Autodesk Fusion 360 part; units mm, degrees
(part 2 of 2)
sketch "Esboço2 (11)" plane through (83, 0, 0) normal (1, 0, 0) x (0, 0, -1) in component "08 / Cursor lateral ON OFF / aciona chave da placa"
  line L0 (7, 35.82) -> (11, 35.82)
  line L1 (11.5, 36.32) -> (11.5, 39.32)
  line L2 (11, 39.82) -> (7, 39.82)
  line L3 (6.5, 39.32) -> (6.5, 36.32)
  arc A0 (11, 35.82) -> (11.5, 36.32) centre (11, 36.32) ccw
  arc A1 (11.5, 39.32) -> (11, 39.82) centre (11, 39.32) ccw
  arc A2 (7, 39.82) -> (6.5, 39.32) centre (7, 39.32) ccw
  arc A3 (6.5, 36.32) -> (7, 35.82) centre (7, 36.32) ccw
extrude "Ponte do cursor ate a chave" add sketch "Esboço2 (11)" along normal blind 6 bodies 17 in component "08 / Cursor lateral ON OFF / aciona chave da placa"
ref_plane "Plano de trabalho3" through (85, 0, 0) normal (1, 0, 0) x (0, 1, 0) in component "08 / Cursor lateral ON OFF / aciona chave da placa"
sketch "Esboço3 (7)" plane through (85, 0, 0) normal (1, 0, 0) x (0, 0, -1) in component "08 / Cursor lateral ON OFF / aciona chave da placa"
  line L0 (2, 32.82) -> (16, 32.82)
  line L1 (18, 34.82) -> (18, 40.82)
  line L2 (16, 42.82) -> (2, 42.82)
  line L3 (0, 40.82) -> (0, 34.82)
  arc A0 (16, 32.82) -> (18, 34.82) centre (16, 34.82) ccw
  arc A1 (18, 40.82) -> (16, 42.82) centre (16, 40.82) ccw
  arc A2 (2, 42.82) -> (0, 40.82) centre (2, 40.82) ccw
  arc A3 (0, 34.82) -> (2, 32.82) centre (2, 34.82) ccw
extrude "Flange de retencao" add sketch "Esboço3 (7)" along normal blind 1.2 bodies 17 in component "08 / Cursor lateral ON OFF / aciona chave da placa"
ref_plane "Plano de trabalho4" through (82, 0, 0) normal (1, 0, 0) x (0, 1, 0) in component "08 / Cursor lateral ON OFF / aciona chave da placa"
sketch "Esboço4 (5)" plane through (82, 0, 0) normal (1, 0, 0) x (0, 0, -1) in component "08 / Cursor lateral ON OFF / aciona chave da placa"
  line L0 (7, 35.82) -> (11, 35.82)
  line L1 (11.5, 36.32) -> (11.5, 39.32)
  line L2 (11, 39.82) -> (7, 39.82)
  line L3 (6.5, 39.32) -> (6.5, 36.32)
  arc A0 (11, 35.82) -> (11.5, 36.32) centre (11, 36.32) ccw
  arc A1 (11.5, 39.32) -> (11, 39.82) centre (11, 39.32) ccw
  arc A2 (7, 39.82) -> (6.5, 39.32) centre (7, 39.32) ccw
  arc A3 (6.5, 36.32) -> (7, 35.82) centre (7, 36.32) ccw
extrude "Garfo chave / medir lingueta" add sketch "Esboço4 (5)" along normal blind 2.2 bodies 17 in component "08 / Cursor lateral ON OFF / aciona chave da placa"
ref_plane "Plano de trabalho5" through (81.9, 0, 0) normal (1, 0, 0) x (0, 1, 0) in component "08 / Cursor lateral ON OFF / aciona chave da placa"
sketch "Esboço5 (5)" plane through (81.9, 0, 0) normal (1, 0, 0) x (0, 0, -1) in component "08 / Cursor lateral ON OFF / aciona chave da placa"
  line L0 (8.3, 36.82) -> (9.7, 36.82)
  line L1 (10, 37.12) -> (10, 38.52)
  line L2 (9.7, 38.82) -> (8.3, 38.82)
  line L3 (8, 38.52) -> (8, 37.12)
  arc A0 (9.7, 36.82) -> (10, 37.12) centre (9.7, 37.12) ccw
  arc A1 (10, 38.52) -> (9.7, 38.82) centre (9.7, 38.52) ccw
  arc A2 (8.3, 38.82) -> (8, 38.52) centre (8.3, 38.52) ccw
  arc A3 (8, 37.12) -> (8.3, 36.82) centre (8.3, 37.12) ccw
extrude "Rasgo para lingueta original" cut sketch "Esboço5 (5)" along normal blind 2.3 bodies 17 in component "08 / Cursor lateral ON OFF / aciona chave da placa"
ref_plane "Plano de trabalho1" through (0, 0, -3) normal (0, 0, 1) x (1, 0, 0) in component "09 / Bicos MIC frontais / dutos a medir"
sketch "Esboço1 (12)" plane through (0, 0, -3) normal (0, 0, 1) x (1, 0, 0) in component "09 / Bicos MIC frontais / dutos a medir"
  circle A0 centre (-68, -52.2) radius 1.8
  circle A1 centre (-68, -52.2) radius 1
extrude "Extrusão1" add sketch "Esboço1 (12)" against normal blind 3 separate body makes body 18 in component "09 / Bicos MIC frontais / dutos a medir"
ref_plane "Plano de trabalho2" through (0, 0, -3) normal (0, 0, 1) x (1, 0, 0) in component "09 / Bicos MIC frontais / dutos a medir"
sketch "Esboço2 (12)" plane through (0, 0, -3) normal (0, 0, 1) x (1, 0, 0) in component "09 / Bicos MIC frontais / dutos a medir"
  circle A0 centre (73, -52.2) radius 1.8
  circle A1 centre (73, -52.2) radius 1
extrude "Extrusão2'" add sketch "Esboço2 (12)" against normal blind 3 separate body makes body 19 in component "09 / Bicos MIC frontais / dutos a medir"
component "01 / Moldura fina / microfones frontais" placed x (1, 0, 0) y (0, 1, 0) z (0, 0, 1) at (0, 0, 0)
component "REF / Vidro 164.28 x 99.17 / area ativa assimetrica" placed x (1, 0, 0) y (0, 0.309017, 0.951057) z (0, -0.951057, 0.309017) at (0, 16.9959, 52.3081)
component "02 / Corpo em cunha / apoio direto na mesa" placed x (1, 0, 0) y (0, 0.309017, 0.951057) z (0, -0.951057, 0.309017) at (0, 16.9959, 52.3081)
component "03 / Tampa traseira / grelha alto-falante + ventilacao" placed x (1, 0, 0) y (0, 0.309017, 0.951057) z (0, -0.951057, 0.309017) at (0, 16.9959, 52.3081)
component "REF / PCB 164 x 97 / pitch furos 156 x 89" placed x (1, 0, 0) y (0, 0.309017, 0.951057) z (0, -0.951057, 0.309017) at (0, 16.9959, 52.3081)
component "04 / Apoios PCB / distancias da foto" placed x (1, 0, 0) y (0, 0.309017, 0.951057) z (0, -0.951057, 0.309017) at (0, 16.9959, 52.3081)
component "REF / Alto-falante TRASEIRO / dimensoes provisÃ³rias" placed x (1, 0, 0) y (0, 0.309017, 0.951057) z (0, -0.951057, 0.309017) at (0, 16.9959, 52.3081)
component "05 / Berco traseiro alto-falante / medir encaixe" placed x (1, 0, 0) y (0, 0.309017, 0.951057) z (0, -0.951057, 0.309017) at (0, 16.9959, 52.3081)
component "06 / Volume + e - / teclas no topo" placed x (1, 0, 0) y (0, 0.309017, 0.951057) z (0, -0.951057, 0.309017) at (0, 16.9959, 52.3081)
component "07 / Suporte dos switches volume / eletrica pendente" placed x (1, 0, 0) y (0, 0.309017, 0.951057) z (0, -0.951057, 0.309017) at (0, 16.9959, 52.3081)
component "08 / Cursor lateral ON OFF / aciona chave da placa" placed x (1, 0, 0) y (0, 0.309017, 0.951057) z (0, -0.951057, 0.309017) at (0, 16.9959, 52.3081)
component "09 / Bicos MIC frontais / dutos a medir" placed x (1, 0, 0) y (0, 0.309017, 0.951057) z (0, -0.951057, 0.309017) at (0, 16.9959, 52.3081)
equation "wall = 2.4 mm" comment "Parede da carcaca"
equation "bezel = 3 mm" comment "Moldura frontal"
equation "rear_cover = 2.4 mm" comment "Tampa traseira"
equation "pcb_holes_x = 156 mm" comment "Entre furos da foto"
equation "pcb_holes_y = 89 mm" comment "Entre furos; PCB total 97 mm"
equation "d6 = -bezel"
equation "d30 = wall"
equation "d58 = -rear_cover"
